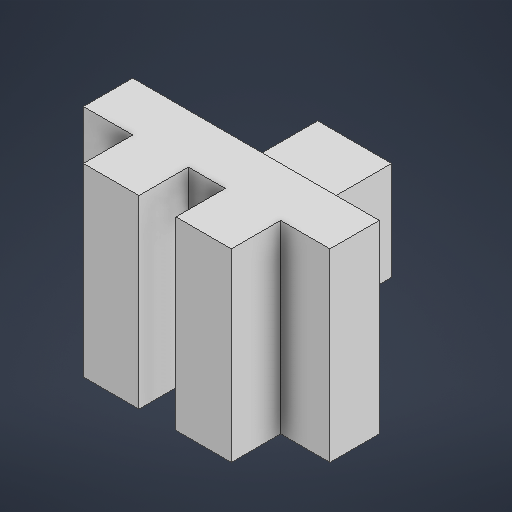
# Autodesk Inventor part: 拨盘
Saved by Autodesk Inventor 2025 (Build 290162000, 162)
## iProperties
Created: 2025-09-27
Part Number: 拨盘
Material: 常规
Document SubType Name: Modeling
Designer: HZD
Density: 1 g/cm^3
Appearance: 默认
Author: HZD
Autodesk Inventor part; units mm, degrees
ref_plane "YZ Plane" through (0, 0, 0) normal (1, 0, 0) x (0, 1, 0)
ref_plane "XZ Plane" through (0, 0, 0) normal (0, 1, 0) x (-1, 0, 0)
ref_plane "XY Plane" through (0, 0, 0) normal (0, 0, 1) x (1, 0, 0)
sketch "草图1" plane through (0, 0, 0) normal (0, 0, 1) x (1, 0, 0)
  line L0 (4, -2.75) -> (-4, -2.75)
  line L1 (-4, -2.75) -> (-4, 2.75)
  line L2 (-4, 2.75) -> (4, 2.75)
  line L3 (4, 2.75) -> (4, -2.75)
  line L4 (4, -2.75) -> (-4, 2.75) construction
  line L5 (-4, -2.75) -> (4, 2.75) construction
  line L6 (5, 3.75) -> (-5, 3.75)
  line L7 (-5, 3.75) -> (-5, -3.75)
  line L8 (-5, -3.75) -> (5, -3.75)
  line L9 (5, -3.75) -> (5, 3.75)
  point P0 (0, 0)
  dimension "d0" = 8
  dimension "d1" = 5.5
  dimension "d2" = 1
  constraints: 20 end point, 4 parallel, 2 midpoint, 2 perpendicular, 1 horizontal, 3 other
  measures "d0" distance of L1.end L2.end
  measures "d1" distance of L2.end L0.start
  measures "d2" distance between parallel lines of L2 L6
extrude "拉伸1" add sketch "草图1" along normal blind 2 contours L0 L1 L2 L3 | L9 L8 L7 L6
sketch "草图2" plane through (0, 0, 2) normal (0, 0, 1) x (1, 0, 0)
  line L0 (5, 3.75) -> (-5, 3.75) projected
  line L1 (-0.746, -3.75) -> (-3, -3.75)
  line L2 (-3, -3.75) -> (-3, 3.75)
  line L3 (-3, 3.75) -> (-0.746, 3.75)
  line L4 (-0.746, 3.75) -> (-0.746, -3.75)
  line L5 (-0.746, -3.75) -> (-3, 3.75) construction
  line L6 (-3, -3.75) -> (-0.746, 3.75) construction
  line L7 (3, -3.75) -> (0.754, -3.75)
  line L8 (0.754, -3.75) -> (0.754, 3.75)
  line L9 (0.754, 3.75) -> (3, 3.75)
  line L10 (3, 3.75) -> (3, -3.75)
  line L11 (3, -3.75) -> (0.754, 3.75) construction
  line L12 (0.754, -3.75) -> (3, 3.75) construction
  line L13 (5, -3.75) -> (5, 3.75) projected
  line L14 (-5, 3.75) -> (-5, -3.75) projected
  line L15 (0.754, 3.75) -> (-0.746, -3.75)
  point P0 (0, 0)
  point P1 (-1.873, 0)
  point P2 (1.877, 0)
  point P3 (3, 3.75)
  point P4 (-0.746, 3.75)
  dimension "d5" = 1.5
  dimension "d6" = 2
  dimension "d7" = 2
  constraints: 26 end point, 4 midpoint, 4 parallel, 2 horizontal, 2 perpendicular, 2 point on line
  measures "d5" distance between parallel lines of L8 L4
  measures "d6" distance between parallel lines of L13 L10
  measures "d7" distance between parallel lines of L14 L2
extrude "拉伸2" add sketch "草图2" along normal blind 2 contours L10 L7 L8 L0 | L4 L1 L2 L0
sketch "草图3" plane through (0, 0, 0) normal (0, 0, -1) x (-1, 0, 0)
  line L0 (-1.5, 2) -> (1.5, 2)
  line L1 (1.5, 2) -> (1.5, -2)
  line L2 (1.5, -2) -> (-1.5, -2)
  line L3 (-1.5, -2) -> (-1.5, 2)
  line L4 (-1.5, 2) -> (1.5, -2) construction
  line L5 (1.5, 2) -> (-1.5, -2) construction
  point P0 (0, 0)
  dimension "d10" = 4
  dimension "d11" = 3
  constraints: 12 end point, 2 midpoint, 2 parallel, 1 horizontal, 1 perpendicular
  measures "d10" distance of L2.end L0.start
  measures "d11" distance between parallel lines of L1 L3
extrude "拉伸3" add sketch "草图3" along normal blind 4
